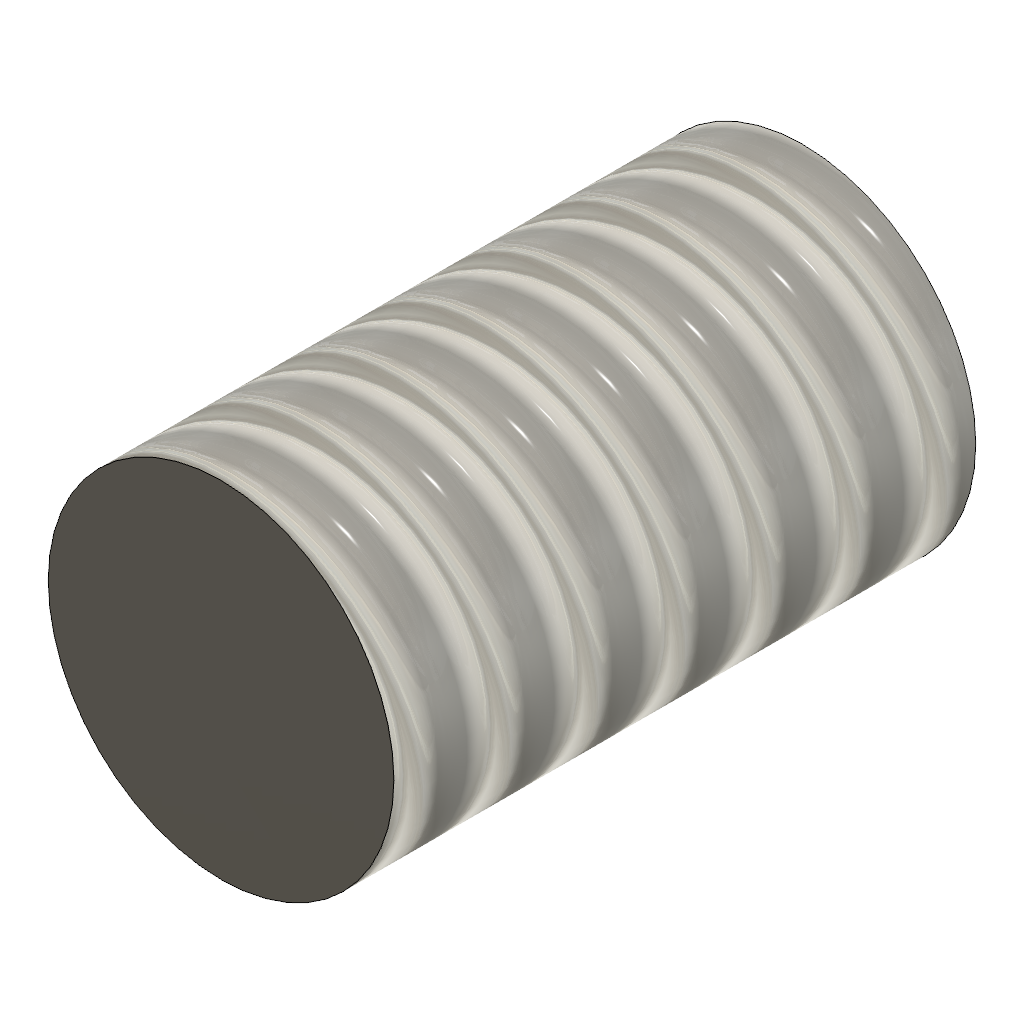
iso_trapezoidal_external (Autodesk Fusion 360 design; units mm, degrees)
part number: 2026-10-21-16-02-15-513
Autodesk Fusion 360 part; units mm, degrees
sketch "OwnedThreadProfile_0_iso_trapezoidal_external" plane through (0, 0, 0) normal (0, 0, 1) x (1, 0, 0)
  circle A0 centre (0, 0) radius 6
extrude "OwnedThreadCylinderExtrude_0_iso_trapezoidal_external" add sketch "OwnedThreadProfile_0_iso_trapezoidal_external" along normal blind 20
thread "OwnedThreadFamily_iso_trapezoidal_external" "ISO Metric Trapezoidal Threads 12.0 TR12x3 TR12x3 7e" major diameter 11.882 minor diameter 8.3175 pitch 3 angle 30 resizes the face on face at (5.9925, -0.2991, 13.3333)
named bodies: "OwnedThreadCylinder_0_iso_trapezoidal_external"
